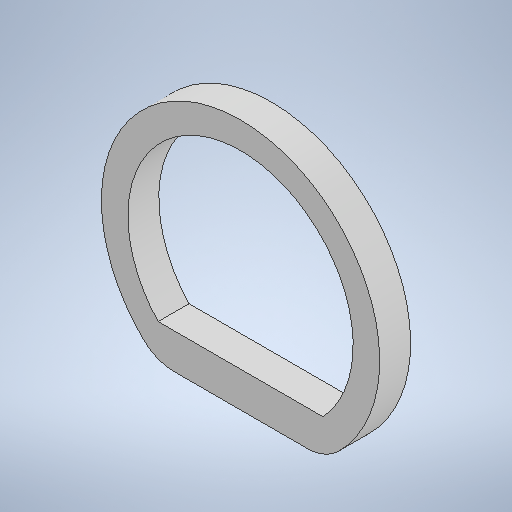
# Autodesk Inventor part: 3D_inner-holder2
Saved by Autodesk Inventor 2025.3 (Build 293356030, 356C)
## iProperties
Created: 2026-02-24
Part Number: 3D_inner-holder2
Material: 一般
Document SubType Name: Modeling
Designer: ibuki_ono
Density: 1 g/cm^3
Appearance: 既定
Author: ibuki_ono
## iProperties of the stored document 3D_inner-holder2_3D プリント.ipt
Created: 2026-02-24
Part Number: 3D_inner-holder2_3D プリント
Material: 一般
Document SubType Name: Modeling
Designer: ibuki_ono
Density: 1 g/cm^3
Appearance: 既定
Author: ibuki_ono
Autodesk Inventor part; units mm, degrees
ref_plane "YZ Plane" through (0, 0, 0) normal (1, 0, 0) x (0, 1, 0)
ref_plane "XZ Plane" through (0, 0, 0) normal (0, 1, 0) x (-1, 0, 0)
ref_plane "XY Plane" through (0, 0, 0) normal (0, 0, 1) x (1, 0, 0)
sketch "スケッチ1" plane through (0, 0, 0) normal (0, 0, 1) x (1, 0, 0)
  circle A0 centre (0, 0) radius 31.5
  circle A1 centre (0, 0) radius 25.5
  line L0 (-18.6644, -25.375) -> (18.6644, -25.375)
  line L1 (18.6644, -25.375) -> (18.6644, -17.375)
  line L2 (18.6644, -17.375) -> (-18.6644, -17.375)
  line L3 (-18.6644, -17.375) -> (-18.6644, -25.375)
  point P0 (-18.6644, -17.375)
  dimension "d0" = 63
  dimension "d1" = 6
  dimension "d2" = 8
  constraints: 8 end point, 2 parallel, 2 point on circle, 1 centre point, 1 coincident, 1 horizontal, 1 perpendicular, 3 other
  measures "d0" diameter of A0
  measures "d2" distance of L0.end L1.end
extrude "押し出し1" add sketch "スケッチ1" along normal mid plane 7 contours A0 L1 A1 L3 | L3 A1 L0 | L0 A1 L1 | A1 L2 L0
fillet "フィレット1" radius 10 2 edges at (18.6644, -25.375, 0) (-18.6644, -25.375, 0)
